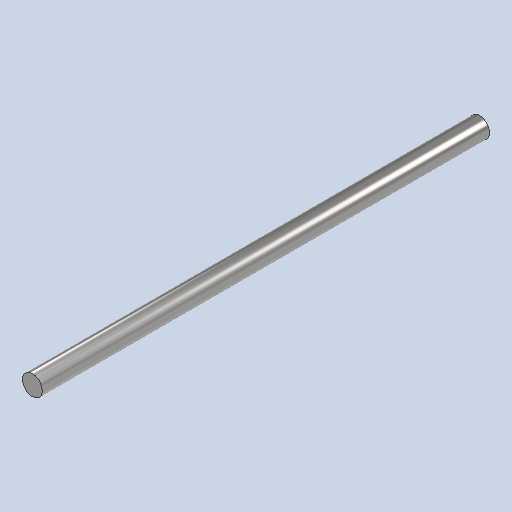
# Autodesk Inventor part: RDS-1501 Mixer Shaft 1
Saved by Autodesk Inventor 2026.2 (Build 302298000, 298)
## iProperties
Created: 2026-10-18
Part Number: RDS-1501 Mixer Shaft 1
Material: Stainless Steel, Austenitic
Description: Mixer shaft 1, rough
Document SubType Name: Modeling
Designer: admin
Stock Number: Вал 1 мешалки (от мотор-редуктора до стыка)
Density: 8 g/cm^3
Appearance: Semi-Polished
Author: admin
Autodesk Inventor part; units mm, degrees
ref_plane "YZ Plane" through (0, 0, 0) normal (1, 0, 0) x (0, 1, 0)
ref_plane "XZ Plane" through (0, 0, 0) normal (0, 1, 0) x (-1, 0, 0)
ref_plane "XY Plane" through (0, 0, 0) normal (0, 0, 1) x (1, 0, 0)
sketch "Sketch1" plane through (0, 0, 0) normal (0, 0, 1) x (1, 0, 0)
  circle A0 centre (0, 0) radius 12.5
  constraints: 1 centre point
extrude "Extrusion1" add sketch "Sketch1" along normal blind 560
equation "\"d0\" = Shaft1501_Length"
equation "\"Shaft1501_Diam\" = 25"
equation "\"Shaft1501_Length\" = 560"
body "Solid1"
